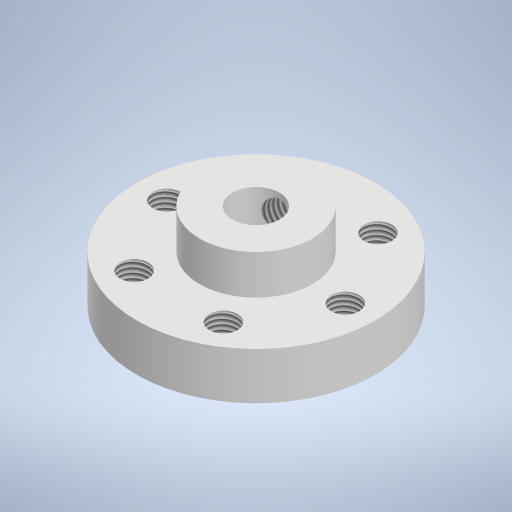
# Autodesk Inventor part: подшипник большой
Saved by Autodesk Inventor 2024.2 (Build 282272000, 272)
## iProperties
Created: 2026-11-10
Part Number: подшипник большой
Material: Типовые
Document SubType Name: Modeling
Designer: katya_notebook
Density: 1 g/cm^3
Appearance: По умолчанию
Author: katya_notebook
Autodesk Inventor part; units mm, degrees
ref_plane "YZ Plane" through (0, 0, 0) normal (1, 0, 0) x (0, 1, 0)
ref_plane "XZ Plane" through (0, 0, 0) normal (0, 1, 0) x (-1, 0, 0)
ref_plane "XY Plane" through (0, 0, 0) normal (0, 0, 1) x (1, 0, 0)
sketch "Эскиз1" plane through (0, 0, 0) normal (0, 1, 0) x (-1, 0, 0)
  circle A0 centre (0, 0) radius 12.7
  circle A1 centre (0, 0) radius 9.5 construction
  circle A2 centre (9.5, 0) radius 1.5
  circle A3 centre (4.75, -8.2272) radius 1.5
  circle A4 centre (-4.75, -8.2272) radius 1.5
  circle A5 centre (-9.5, 0) radius 1.5
  circle A6 centre (-4.75, 8.2272) radius 1.5
  circle A7 centre (4.75, 8.2272) radius 1.5
  circle A8 centre (0, 0) radius 2.5
  dimension "d1" = 19
  dimension "d0" = 25.4
  dimension "d2" = 3
  dimension "d5" = 360
  dimension "d13" = 5
  constraints: 8 centre point, 3 coincident, 1 horizontal alignment, 15 other
  measures "d0" diameter of A0
  measures "d2" diameter of A2
  measures "d13" diameter of A8
extrude "Выдавливание1" add sketch "Эскиз1" along normal blind 5
sketch "Эскиз2" plane through (0, 5, 0) normal (0, 1, 0) x (1, 0, 0)
  circle A0 centre (0, 0) radius 6
  circle A1 centre (0, 0) radius 2.5
  dimension "d9" = 12
  dimension "d10" = 5
  constraints: 2 centre point, 2 coincident
  measures "d9" diameter of A0
  measures "d10" diameter of A1
extrude "Выдавливание2" add sketch "Эскиз2" along normal blind 4.2
sketch "Эскиз3" plane through (0, 0, 0) normal (0, 0, 1) x (0, 1, 0)
  line L0 (5, -12.7) -> (5, 12.7) projected
  line L1 (0, -12.7) -> (0, 12.7) projected
  line L2 (5, 12.7) -> (0, 12.7)
  line L3 (0, 12.7) -> (0, -12.7)
  line L4 (0, -12.7) -> (5, -12.7)
  line L5 (5, -12.7) -> (5, 12.7)
  line L6 (9.2, -6) -> (9.2, 6) projected
  line L7 (9.2, 6) -> (5, 6)
  line L8 (5, 6) -> (5, -6)
  line L9 (5, -6) -> (9.2, -6)
  line L10 (9.2, -6) -> (9.2, 6)
  line L11 (11.8051, 0) -> (-3.6863, 0) construction
  line L12 (5, 12.7) -> (0, -12.7) construction
  line L13 (0, 12.7) -> (5, -12.7) construction
  line L14 (5, -6) -> (9.2, 6) construction
  line L15 (5, 6) -> (9.2, -6) construction
  circle A0 centre (2.5, 0) radius 1.5
  circle A1 centre (7.1, 0) radius 1.5
  point P0 (0, 0)
  dimension "d14" = 3
  dimension "d15" = 3
  constraints: 26 end point, 4 parallel, 3 horizontal, 2 centre point, 2 midpoint, 2 perpendicular, 1 point on line
  measures "d14" diameter of A1
  measures "d15" diameter of A0
extrude "Выдавливание4" cut sketch "Эскиз3" against normal blind 14 contours A0 | A1
thread "Резьба1" size "M3x0.5" class "6H" standard "ANSI Metric M Profile" full length
thread "Резьба2" size "M3x0.5" class "6H" standard "ANSI Metric M Profile" full length
thread "Резьба3" size "M3x0.5" class "6H" standard "ANSI Metric M Profile" full length
thread "Резьба4" size "M3x0.5" class "6H" standard "ANSI Metric M Profile" full length
thread "Резьба5" size "M3x0.5" class "6H" standard "ANSI Metric M Profile" full length
thread "Резьба6" size "M3x0.5" class "6H" standard "ANSI Metric M Profile" full length
thread "Резьба7" size "M3x0.5" class "6H" standard "ANSI Metric M Profile" full length
thread "Резьба8" size "M3x0.5" class "6H" standard "ANSI Metric M Profile" full length
